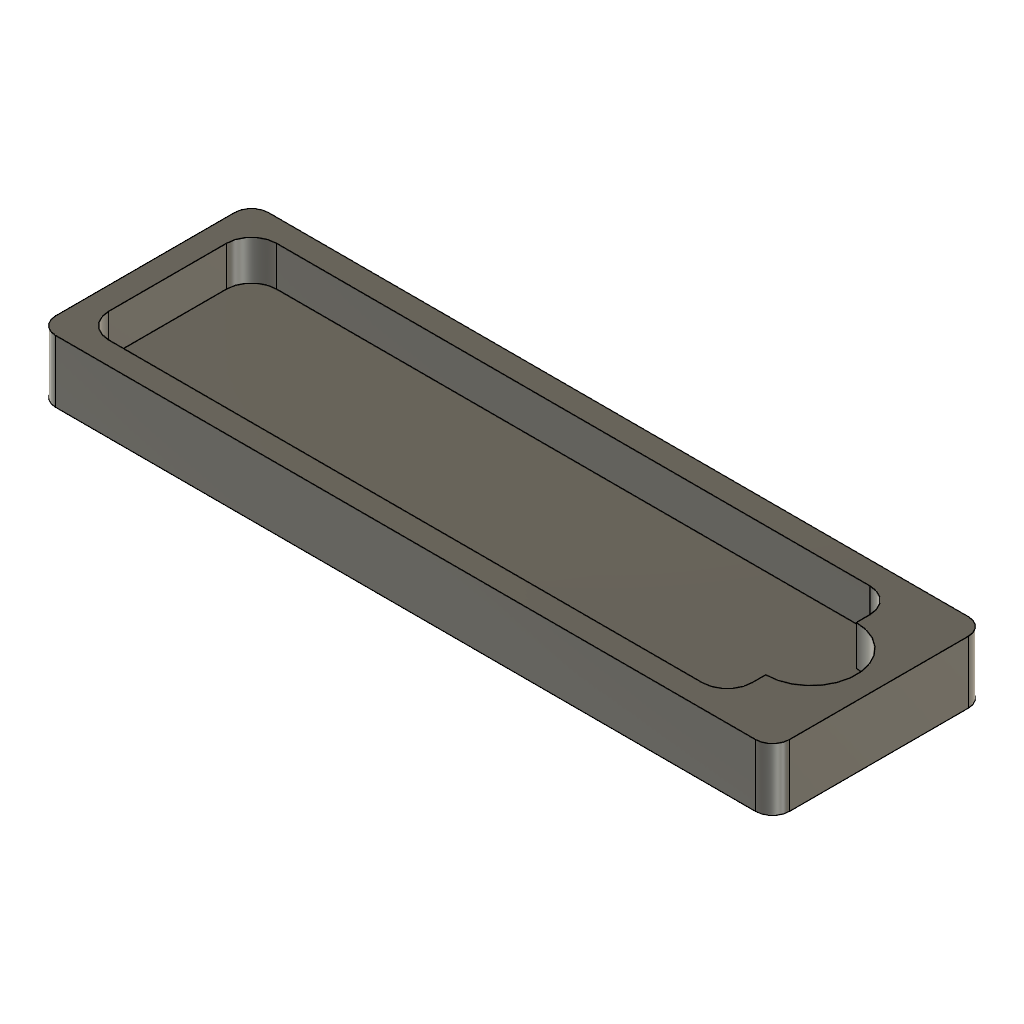
stand_test_depth3p5_fingerD8_NOT_FOR_MANUFACTURE (Autodesk Fusion 360 design; units mm, degrees)
part number: 2026-11-08-15-08-38-650
Autodesk Fusion 360 part; units mm, degrees
sketch "スケッチ1" plane through (0, 0, 0) normal (0, 0, 1) x (1, 0, 0)
  line L0 (1.5, 0) -> (63.3, 0)
  line L1 (64.8, 1.5) -> (64.8, 17.3)
  line L2 (63.3, 18.8) -> (1.5, 18.8)
  line L3 (0, 17.3) -> (0, 1.5)
  arc A0 (63.3, 0) -> (64.8, 1.5) centre (63.3, 1.5) ccw
  arc A1 (64.8, 17.3) -> (63.3, 18.8) centre (63.3, 17.3) ccw
  arc A2 (1.5, 18.8) -> (0, 17.3) centre (1.5, 17.3) ccw
  arc A3 (0, 1.5) -> (1.5, 0) centre (1.5, 1.5) ccw
extrude "押し出し1" add sketch "スケッチ1" along normal blind 5.5
ref_plane "作業平面1" through (0, 0, 2) normal (0, 0, 1) x (1, 0, 0)
sketch "スケッチ2" plane through (0, 0, 2) normal (0, 0, 1) x (1, 0, 0)
  line L0 (4.2, 2) -> (56.6, 2)
  line L1 (58.8, 4.2) -> (58.8, 14.6)
  line L2 (56.6, 16.8) -> (4.2, 16.8)
  line L3 (2, 14.6) -> (2, 4.2)
  arc A0 (56.6, 2) -> (58.8, 4.2) centre (56.6, 4.2) ccw
  arc A1 (58.8, 14.6) -> (56.6, 16.8) centre (56.6, 14.6) ccw
  arc A2 (4.2, 16.8) -> (2, 14.6) centre (4.2, 14.6) ccw
  arc A3 (2, 4.2) -> (4.2, 2) centre (4.2, 4.2) ccw
extrude "Stand_pocket_56p8x14p8_R2p2_depth3p5" cut sketch "スケッチ2" along normal blind 3.5
sketch "スケッチ3" plane through (0, 0, 2) normal (0, 0, 1) x (1, 0, 0)
  circle A0 centre (58.8, 9.4) radius 4
extrude "Finger_access_D8_same_depth" cut sketch "スケッチ3" along normal blind 3.5
